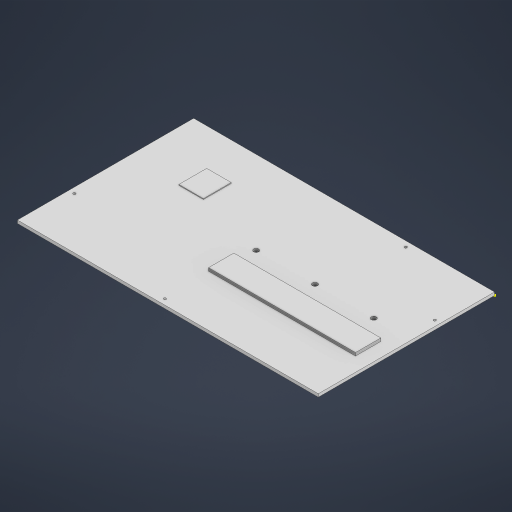
# Autodesk Inventor part: Kühler_QZSI
Saved by Autodesk Inventor 2024.3 (Build 283343000, 343)
## iProperties
Created: 2026-09-02
Part Number: Kühler_QZSI
Material: Generisch
Document SubType Name: Modeling
Designer: Augschöll_F
Density: 1 g/cm^3
Appearance: Vorgabe
Mass: 50.6291 g
Surface Area: 490.318 cm^2
Volume: 50.6291 cm^3
Author: Augschöll_F
Autodesk Inventor part; units mm, degrees
ref_plane "YZ Plane" through (0, 0, 0) normal (1, 0, 0) x (0, 1, 0)
ref_plane "XZ Plane" through (0, 0, 0) normal (0, 1, 0) x (-1, 0, 0)
ref_plane "XY Plane" through (0, 0, 0) normal (0, 0, 1) x (1, 0, 0)
sketch "Skizze2" plane through (0, 0, 0) normal (0, 0, 1) x (1, 0, 0)
  line L0 (0, 0) -> (200.8, 0)
  line L1 (200.8, 0) -> (200.8, -117.6)
  line L2 (200.8, -117.6) -> (0, -117.6)
  line L3 (0, -117.6) -> (0, 0)
  dimension "d0" = 200.8
  dimension "d1" = 117.6
  constraints: 8 end point, 2 parallel, 1 horizontal, 1 perpendicular
  measures "d0" distance of L0.start L0.end
  measures "d1" distance of L2.end L0.start
extrude "Extrusion1" add sketch "Skizze2" along normal blind 2
sketch "Skizze3" plane through (0, 0, 2) normal (0, 0, 1) x (1, 0, 0)
  line L0 (200.8, 0) -> (0, 0) projected
  line L1 (0, 0) -> (0, -117.6) projected
  point P0 (145.2, -3.7)
  point P1 (197.1, -36.2)
  point P2 (94.7, -113.9)
  point P3 (3.7, -83.3)
  dimension "d4" = 3.7
  dimension "d5" = 145.2
  dimension "d6" = 197.1
  dimension "d7" = 36.2
  dimension "d8" = 94.7
  dimension "d9" = 113.9
  dimension "d10" = 3.7
  dimension "d11" = 83.3
  measures "d4" distance from line of L0 point (145.2, -3.7)
  measures "d5" distance from line of L1 point (145.2, -3.7)
  measures "d6" distance from line of L1 point (197.1, -36.2)
  measures "d7" distance from line of L0 point (197.1, -36.2)
  measures "d8" distance from line of L1 point (94.7, -113.9)
  measures "d9" distance from line of point (94.7, -113.9) L0
  measures "d10" distance from line of L1 point (3.7, -83.3)
  measures "d11" distance from line of L0 point (3.7, -83.3)
hole "Bohrung1" at (145.2, -3.7, 2) at (197.1, -36.2, 2) at (94.7, -113.9, 2) at (3.7, -83.3, 2) direction (0, 0, -1) diameter 1.6 depth 4
sketch "Skizze4" plane through (0, 0, 2) normal (0, 0, 1) x (1, 0, 0)
  line L0 (93.3, -66.5) -> (191.4, -66.5)
  line L1 (191.4, -66.5) -> (191.4, -83.4)
  line L2 (191.4, -83.4) -> (93.3, -83.4)
  line L3 (93.3, -83.4) -> (93.3, -66.5)
  line L4 (0, -117.6) -> (200.8, -117.6) projected
  line L5 (200.8, -117.6) -> (200.8, 0) projected
  point P0 (0, 0)
  point P1 (142.35, -83.4)
  point P2 (191.4, -74.95)
  dimension "d19" = 34.2
  dimension "d20" = 9.4
  dimension "d21" = 16.9
  dimension "d22" = 98.1
  constraints: 8 end point, 2 midpoint, 2 parallel, 1 horizontal, 1 perpendicular
  measures "d19" distance from line of L4 point (142.35, -83.4)
  measures "d20" distance from line of L5 point (191.4, -74.95)
  measures "d21" distance of L2.end L0.start
  measures "d22" distance of L0.start L0.end
extrude "Extrusion2" add sketch "Skizze4" along normal blind 2
sketch "Skizze5" plane through (0, 0, 2) normal (0, 0, 1) x (1, 0, 0)
  line L0 (33.8, -25.1) -> (50.2, -25.1)
  line L1 (50.2, -25.1) -> (50.2, -43.7)
  line L2 (50.2, -43.7) -> (33.8, -43.7)
  line L3 (33.8, -43.7) -> (33.8, -25.1)
  line L4 (0, 0) -> (0, -117.6) projected
  line L5 (200.8, 0) -> (0, 0) projected
  dimension "d25" = 33.8
  dimension "d26" = 25.1
  dimension "d27" = 18.6
  dimension "d28" = 16.4
  constraints: 8 end point, 2 parallel, 1 horizontal, 1 perpendicular
  measures "d25" distance between parallel lines of L4 L3
  measures "d26" distance between parallel lines of L5 L0
  measures "d27" distance of L0.end L1.end
  measures "d28" distance of L0.start L0.end
extrude "Extrusion3" add sketch "Skizze5" along normal blind 0.5
sketch "Skizze6" plane through (0, 0, 2) normal (0, 0, 1) x (1, 0, 0)
  line L0 (0, 0) -> (0, -117.6) projected
  line L1 (200.8, 0) -> (0, 0) projected
  point P0 (97.23, -55.5)
  point P1 (136.474, -55.5)
  point P2 (175.72, -55.5)
  dimension "d31" = 97.23
  dimension "d32" = 55.5
  dimension "d33" = 136.474
  dimension "d34" = 175.72
  constraints: 2 horizontal alignment
  measures "d31" distance from line of L0 point (97.23, -55.5)
  measures "d32" distance from line of L1 point (97.23, -55.5)
  measures "d33" distance from line of L0 point (136.474, -55.5)
  measures "d34" distance from line of L0 point (175.72, -55.5)
hole "Bohrung2" at (97.23, -55.5, 2) at (136.474, -55.5, 2) at (175.72, -55.5, 2) direction (0, 0, -1) diameter 3.3 depth 4
sketch "Skizze7" plane through (0, 0, 0) normal (0, 0, -1) x (-1, 0, 0)
  line L0 (-88.1464, -92.4545) -> (-74.7732, -92.4545) construction
  line L1 (-74.7732, -92.4545) -> (-74.7732, -96.9444) construction
  line L2 (-74.7732, -96.9444) -> (-88.1464, -96.9444) construction
  line L3 (-88.1464, -96.9444) -> (-88.1464, -92.4545) construction
  point P0 (-200.8, 0)
  dimension "d3" = 0
  constraints: 2 other
